Lid (Autodesk Fusion 360 design; units mm, degrees)
Autodesk Fusion 360 part; units mm, degrees
sketch "Sketch1" plane through (0, 0, 0) normal (0, 1, 0) x (1, 0, 0)
  line L0 (14.425, -21.7) -> (-14.425, -21.7)
  line L1 (-14.425, -21.7) -> (-14.425, 21.7)
  line L2 (-14.425, 21.7) -> (14.425, 21.7)
  line L3 (14.425, 21.7) -> (14.425, -21.7)
  line L4 (14.425, -21.7) -> (-14.425, 21.7) construction
  line L5 (-14.425, -21.7) -> (14.425, 21.7) construction
  line L6 (2, 17.7) -> (-2, 17.7)
  line L7 (-2, 17.7) -> (-2, 25.7)
  line L8 (-2, 25.7) -> (2, 25.7)
  line L9 (2, 25.7) -> (2, 17.7)
  line L10 (2, 17.7) -> (-2, 25.7) construction
  line L11 (-2, 17.7) -> (2, 25.7) construction
  line L12 (2, -25.7) -> (-2, -25.7)
  line L13 (-2, -25.7) -> (-2, -17.7)
  line L14 (-2, -17.7) -> (2, -17.7)
  line L15 (2, -17.7) -> (2, -25.7)
  line L16 (2, -25.7) -> (-2, -17.7) construction
  line L17 (-2, -25.7) -> (2, -17.7) construction
  point P0 (0, 21.7)
  point P1 (0, -21.7)
  dimension "d1" = 28.85
  dimension "d2" = 43.4
  dimension "d3" = 4
  dimension "d4" = 8
  dimension "d5" = 8
  dimension "d6" = 4
  constraint perpendicular L0 L1
  constraint parallel L0 L2
  constraint parallel L1 L3
  constraint horizontal L0
  constraint coincident L4 origin
  constraint coincident L5 origin
  constraint perpendicular L6 L7
  constraint parallel L6 L8
  constraint parallel L7 L9
  constraint horizontal L6
  constraint coincident L10 P0
  constraint coincident L11 P0
  constraint midpoint L2 P0
  constraint perpendicular L12 L13
  constraint parallel L12 L14
  constraint parallel L13 L15
  constraint horizontal L12
  constraint coincident L16 P1
  constraint coincident L17 P1
  constraint midpoint L0 P1
  measures "d1" distance of L1.end L2.end
  measures "d2" distance of L0.end L2.start L1
  measures "d3" distance of L7.end L8.end
  measures "d4" distance of L6.end L7.end
  measures "d5" distance of L12.end L13.end L1
  measures "d6" distance of L13.end L14.end
extrude "Extrude1" add sketch "Sketch1" along normal blind 3
sketch "Sketch2" plane through (0, 3, 0) normal (0, 1, 0) x (-1, 0, 0)
  line L0 (-14.425, 21.7) -> (-14.425, -21.7)
  line L1 (-14.425, -21.7) -> (-2, -21.7)
  line L2 (-2, -21.7) -> (-2, -25.7)
  line L3 (-2, -25.7) -> (2, -25.7)
  line L4 (2, -25.7) -> (2, -21.7)
  line L5 (2, -21.7) -> (14.425, -21.7)
  line L6 (14.425, -21.7) -> (14.425, 21.7)
  line L7 (14.425, 21.7) -> (2, 21.7)
  line L8 (2, 21.7) -> (2, 25.7)
  line L9 (2, 25.7) -> (-2, 25.7)
  line L10 (-2, 25.7) -> (-2, 21.7)
  line L11 (-2, 21.7) -> (-14.425, 21.7)
  line L12 (2, 23.7) -> (-12.6116, 23.7) construction
  line L13 (2, -23.7) -> (-12.7099, -23.7) construction
  line L14 (0, -25.7) -> (0, -20.5021) construction
  line L15 (0, 25.7) -> (0, 22.5765) construction
  circle A0 centre (0, 23.7) radius 1.375
  circle A1 centre (0, -23.7) radius 1.375
  dimension "d9" = 2.75
  dimension "d10" = 2.75
  constraint midpoint L8 L12.start
  constraint perpendicular L8 L12
  constraint midpoint L4 L13.start
  constraint perpendicular L4 L13
  constraint midpoint L3 L14.start
  constraint perpendicular L3 L14
  constraint midpoint L9 L15.start
  constraint perpendicular L12 L15
  constraint coincident L15 A0.centre
  constraint coincident L12 A0.centre
  constraint coincident L14 A1.centre
  constraint coincident L13 A1.centre
  measures "d9" diameter of A0
  measures "d10" diameter of A1
extrude "Extrude2" cut sketch "Sketch2" against normal up to surface (3 mm away) contours A0 | A1
fillet "Fillet1" radius 2.5 4 edges at (-14.425, 1.5, 21.7) (14.425, 1.5, 21.7) (14.425, 1.5, -21.7) (-14.425, 1.5, -21.7)
sketch "Sketch3" plane through (0, 3, 0) normal (0, 1, 0) x (-1, 0, 0)
  arc A0 (11.925, -21.7) -> (14.425, -19.2) centre (11.925, -19.2) ccw
  line L0 (14.425, -19.2) -> (14.425, 19.2)
  arc A1 (14.425, 19.2) -> (11.925, 21.7) centre (11.925, 19.2) ccw
  line L1 (11.925, 21.7) -> (2, 21.7)
  line L2 (2, 21.7) -> (2, 25.7)
  line L3 (2, 25.7) -> (-2, 25.7)
  line L4 (-2, 25.7) -> (-2, 21.7)
  line L5 (-2, 21.7) -> (-11.925, 21.7)
  arc A2 (-11.925, 21.7) -> (-14.425, 19.2) centre (-11.925, 19.2) ccw
  line L6 (-14.425, 19.2) -> (-14.425, -19.2)
  arc A3 (-14.425, -19.2) -> (-11.925, -21.7) centre (-11.925, -19.2) ccw
  line L7 (-11.925, -21.7) -> (-2, -21.7)
  line L8 (-2, -21.7) -> (-2, -25.7)
  line L9 (-2, -25.7) -> (2, -25.7)
  line L10 (2, -25.7) -> (2, -21.7)
  line L11 (2, -21.7) -> (11.925, -21.7)
  circle A4 centre (0, -23.7) radius 1.375
  circle A5 centre (0, 23.7) radius 1.375
  line L12 (-12.675, 20.2) -> (12.675, 20.2)
  line L13 (12.675, 20.2) -> (12.675, -20.2)
  line L14 (12.675, -20.2) -> (-12.675, -20.2)
  line L15 (-12.675, -20.2) -> (-12.675, 20.2)
  line L16 (-12.675, 20.2) -> (12.675, -20.2) construction
  line L17 (12.675, 20.2) -> (-12.675, -20.2) construction
  line L18 (-11.925, 19.2) -> (11.925, 19.2)
  line L19 (11.925, 19.2) -> (11.925, -19.2)
  line L20 (11.925, -19.2) -> (-11.925, -19.2)
  line L21 (-11.925, -19.2) -> (-11.925, 19.2)
  line L22 (-11.925, 19.2) -> (11.925, -19.2) construction
  line L23 (11.925, 19.2) -> (-11.925, -19.2) construction
  dimension "d14" = 40.4
  dimension "d15" = 25.35
  dimension "d16" = 23.85
  dimension "d17" = 38.4
  constraint perpendicular L12 L13
  constraint parallel L12 L14
  constraint parallel L13 L15
  constraint horizontal L12
  constraint coincident L16 origin
  constraint coincident L17 origin
  constraint perpendicular L18 L19
  constraint parallel L18 L20
  constraint parallel L19 L21
  constraint horizontal L18
  constraint coincident L22 origin
  constraint coincident L23 origin
  measures "d14" distance of L12.end L13.end
  measures "d15" distance of L13.end L14.end
  measures "d16" distance of A0.centre A3.centre
  measures "d17" distance of A1.centre A0.centre
extrude "Extrude3" cut sketch "Sketch3" against normal blind 1 contours L12 L13 L14 L15
fillet "Fillet2" radius 2.5 8 edges at (-12.675, 2.5, -20.2) (-11.925, 2.5, -19.2) (12.675, 2.5, -20.2) (11.925, 2.5, -19.2) (12.675, 2.5, 20.2) (11.925, 2.5, 19.2) (-12.675, 2.5, 20.2) (-11.925, 2.5, 19.2)
chamfer "Chamfer1" distance 4 angle 45 4 edges at (2, 1.5, 21.7) (-2, 1.5, 21.7) (2, 1.5, -21.7) (-2, 1.5, -21.7) tangent chain off
sketch "Sketch4" plane through (14.425, 0, 0) normal (1, 0, 0) x (0, 0, -1)
  line L0 (19.2, 0) -> (19.2, 3)
  line L1 (19.2, 3) -> (-19.2, 3)
  line L2 (-19.2, 3) -> (-19.2, 0)
  line L3 (-19.2, 0) -> (19.2, 0)
  line L4 (2, 1) -> (-2, 1)
  line L5 (-2, 1) -> (-2, 5)
  line L6 (-2, 5) -> (2, 5)
  line L7 (2, 5) -> (2, 1)
  line L8 (2, 1) -> (-2, 5) construction
  line L9 (-2, 1) -> (2, 5) construction
  point P0 (0, 3)
  dimension "d23" = 4
  dimension "d24" = 4
  constraint perpendicular L4 L5
  constraint parallel L4 L6
  constraint parallel L5 L7
  constraint horizontal L4
  constraint coincident L8 P0
  constraint coincident L9 P0
  constraint midpoint L1 P0
  measures "d23" distance of L5.end L6.end
  measures "d24" distance of L4.end L5.end
extrude "Extrude4" add sketch "Sketch4" along normal blind 4 contours L1 L4 L5 L7
sketch "Sketch5" plane through (-14.425, 0, 0) normal (-1, 0, 0) x (0, 0, 1)
  line L0 (-19.2, 3) -> (-19.2, 0)
  line L1 (-19.2, 0) -> (19.2, 0)
  line L2 (19.2, 0) -> (19.2, 3)
  line L3 (19.2, 3) -> (-19.2, 3)
  line L4 (2, 1) -> (-2, 1)
  line L5 (-2, 1) -> (-2, 5)
  line L6 (-2, 5) -> (2, 5)
  line L7 (2, 5) -> (2, 1)
  line L8 (2, 1) -> (-2, 5) construction
  line L9 (-2, 1) -> (2, 5) construction
  point P0 (0, 3)
  dimension "d27" = 4
  dimension "d28" = 4
  constraint perpendicular L4 L5
  constraint parallel L4 L6
  constraint parallel L5 L7
  constraint horizontal L4
  constraint coincident L8 P0
  constraint coincident L9 P0
  constraint midpoint L3 P0
  measures "d27" distance of L5.end L6.end
  measures "d28" distance of L4.end L5.end
extrude "Extrude5" add sketch "Sketch5" along normal blind 4 contours L3 L4 L5 L7
move_face "OffsetFaces1" offset 1 1 faces at (-15.7583, 1, 0.6667)
move_face "OffsetFaces2" offset 1 1 faces at (15.7583, 1, -0.6667)
sketch "Sketch6" plane through (0, 3, 0) normal (0, 1, 0) x (-1, 0, 0)
  circle A0 centre (0, 23.7) radius 1.375
  circle A1 centre (0, -23.7) radius 1.375
  arc A2 (11.925, -21.7) -> (14.425, -19.2) centre (11.925, -19.2) ccw
  line L0 (14.425, -19.2) -> (14.425, -2)
  line L1 (14.425, -2) -> (18.425, -2)
  line L2 (18.425, -2) -> (18.425, 2)
  line L3 (18.425, 2) -> (14.425, 2)
  line L4 (14.425, 2) -> (14.425, 19.2)
  arc A3 (14.425, 19.2) -> (11.925, 21.7) centre (11.925, 19.2) ccw
  line L5 (11.925, 21.7) -> (6, 21.7)
  line L6 (6, 21.7) -> (2, 25.7)
  line L7 (2, 25.7) -> (-2, 25.7)
  line L8 (-2, 25.7) -> (-6, 21.7)
  line L9 (-6, 21.7) -> (-11.925, 21.7)
  arc A4 (-11.925, 21.7) -> (-14.425, 19.2) centre (-11.925, 19.2) ccw
  line L10 (-14.425, 19.2) -> (-14.425, 2)
  line L11 (-14.425, 2) -> (-18.425, 2)
  line L12 (-18.425, 2) -> (-18.425, -2)
  line L13 (-18.425, -2) -> (-14.425, -2)
  line L14 (-14.425, -2) -> (-14.425, -19.2)
  arc A5 (-14.425, -19.2) -> (-11.925, -21.7) centre (-11.925, -19.2) ccw
  line L15 (-11.925, -21.7) -> (-6, -21.7)
  line L16 (-6, -21.7) -> (-2, -25.7)
  line L17 (-2, -25.7) -> (2, -25.7)
  line L18 (2, -25.7) -> (6, -21.7)
  line L19 (6, -21.7) -> (11.925, -21.7)
  line L20 (12.675, 17.7) -> (12.675, -17.7)
  arc A6 (10.175, -20.2) -> (12.675, -17.7) centre (10.175, -17.7) ccw
  line L21 (10.175, -20.2) -> (-10.175, -20.2)
  arc A7 (-12.675, -17.7) -> (-10.175, -20.2) centre (-10.175, -17.7) ccw
  line L22 (-12.675, -17.7) -> (-12.675, 17.7)
  arc A8 (-10.175, 20.2) -> (-12.675, 17.7) centre (-10.175, 17.7) ccw
  line L23 (-10.175, 20.2) -> (10.175, 20.2)
  arc A9 (12.675, 17.7) -> (10.175, 20.2) centre (10.175, 17.7) ccw
  line L24 (-18.425, 0) -> (-16.425, 0)
  circle A10 centre (-16.425, 0) radius 1.375
  line L25 (18.425, 0) -> (16.425, 0)
  circle A11 centre (16.425, 0) radius 1.375
  dimension "d33" = 2
  dimension "d34" = 2.75
  dimension "d35" = 2
  dimension "d36" = 2.75
  constraint midpoint L12 L24.start
  constraint coincident L24.end A10.centre
  constraint midpoint L2 L25.start
  constraint coincident L25.end A11.centre
  measures "d33" distance of L24.start L24.end
  measures "d34" diameter of A10
  measures "d35" distance of L25.start L25.end
  measures "d36" diameter of A11
extrude "Extrude6" cut sketch "Sketch6" against normal up to surface (3 mm away) contours A10 | A11
chamfer "Chamfer2" distance 4 angle 45 4 edges at (14.425, 1.5, 2) (14.425, 1.5, -2) (-14.425, 1.5, -2) (-14.425, 1.5, 2) tangent chain off
